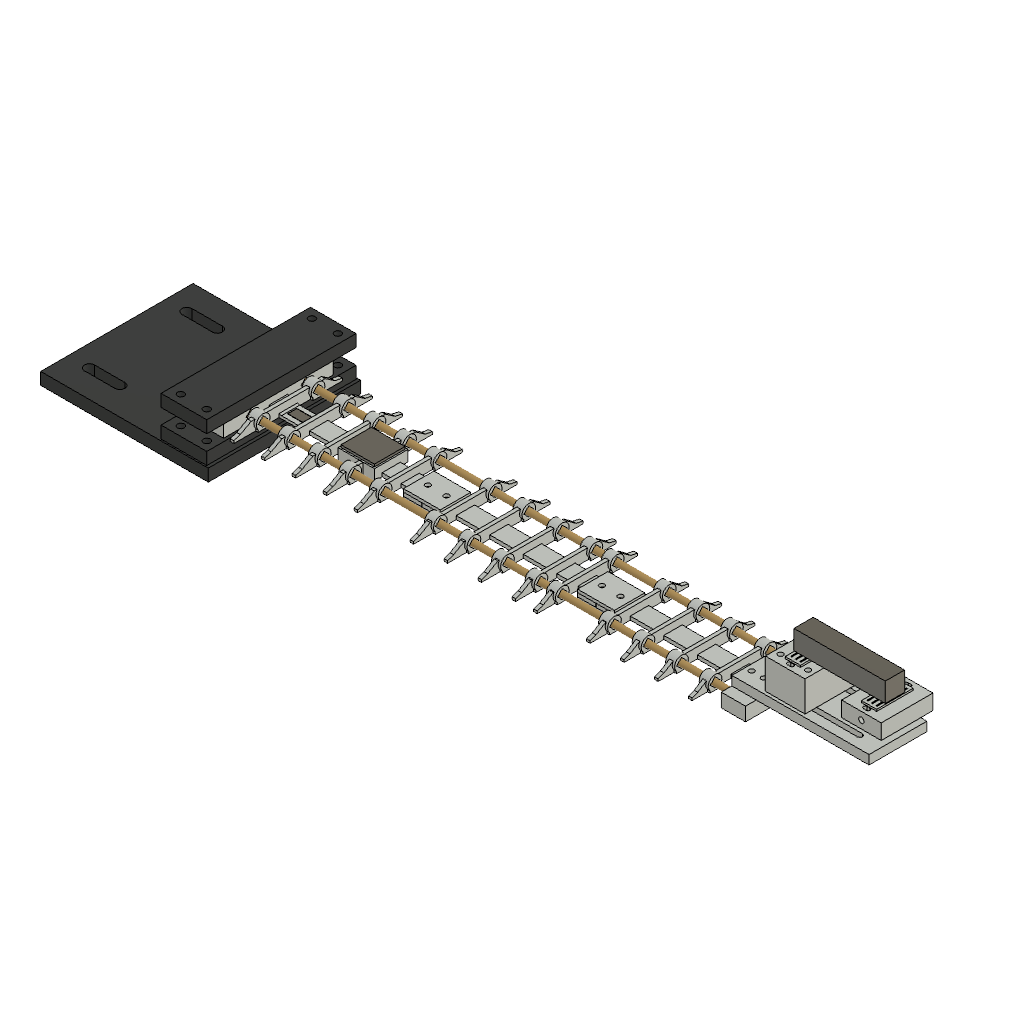
SkySafe_Assembly (Autodesk Fusion 360 design; units mm, degrees)
part number: 2026-10-10-17-05-36-424
part number: 2026-10-10-17-05-36-732
part number: 2026-10-10-17-05-38-635
part number: 2026-10-10-17-05-41-874
part number: 2026-10-10-17-05-46-497
part number: 2026-10-10-17-05-46-997
part number: 2026-10-10-17-05-49-609
part number: 2026-10-10-17-05-50-640
part number: 2026-10-10-17-05-52-144
part number: 2026-10-10-17-05-54-751
part number: 2026-10-10-17-05-56-746
part number: 2026-10-10-17-06-22-756
Autodesk Fusion 360 part; units mm, degrees
(part 1 of 3)
sketch "Continuous connecting strip sketch" plane through (0, 0, 0) normal (0, 0, 1) x (1, 0, 0) in component "01A Wing root - gauge and MPU"
  line L0 (23.95, -6) -> (128, -6)
  line L1 (128, -6) -> (128, 6)
  line L2 (128, 6) -> (23.95, 6)
  line L3 (23.95, 6) -> (23.95, -6)
extrude "Continuous connecting strip" add sketch "Continuous connecting strip sketch" along normal blind 1.8 makes body 1 in component "01A Wing root - gauge and MPU"
sketch "Root tongue sketch" plane through (0, 0, 0) normal (0, 0, 1) x (1, 0, 0) in component "01A Wing root - gauge and MPU"
  line L0 (0, -36) -> (24, -36)
  line L1 (24, -36) -> (24, 36)
  line L2 (24, 36) -> (0, 36)
  line L3 (0, 36) -> (0, -36)
extrude "Root tongue" add sketch "Root tongue sketch" along normal blind 10 bodies 1 in component "01A Wing root - gauge and MPU"
sketch "Reinforced strip beyond gauge sketch" plane through (0, 0, 0) normal (0, 0, 1) x (1, 0, 0) in component "01A Wing root - gauge and MPU"
  line L0 (48, -6) -> (128, -6)
  line L1 (128, -6) -> (128, 6)
  line L2 (128, 6) -> (48, 6)
  line L3 (48, 6) -> (48, -6)
extrude "Reinforced strip beyond gauge" add sketch "Reinforced strip beyond gauge sketch" along normal blind 2.4 bodies 1 in component "01A Wing root - gauge and MPU"
sketch "Root gauge shoulder sketch" plane through (0, 0, 0) normal (0, 1, 0) x (1, 0, 0) in component "01A Wing root - gauge and MPU"
  line L0 (23.95, 0) -> (32, 0)
  line L1 (32, 0) -> (32, -1.8)
  line L2 (32, -1.8) -> (23.95, -4)
  line L3 (23.95, -4) -> (23.95, 0)
extrude "Root tapered gauge shoulder" add sketch "Root gauge shoulder sketch" along normal mid plane 12 bodies 1 in component "01A Wing root - gauge and MPU"
ref_plane "WorkPlane1" through (28, 0, 0) normal (1, 0, 0) x (0, 1, 0) in component "01A Wing root - gauge and MPU"
sketch "Rib at 28 mm sketch" plane through (28, 0, 0) normal (1, 0, 0) x (0, 0, -1) in component "01A Wing root - gauge and MPU"
  line L0 (0, -35.6072) -> (0, 35.6072)
  line L1 (0, 35.6072) -> (-1.6, 35.6072)
  line L2 (-1.6, 35.6072) -> (-2.6, 30.6222)
  line L3 (-2.6, 30.6222) -> (-6.95, 24.2129)
  line L4 (-6.95, 24.2129) -> (-6.95, -24.2129)
  line L5 (-6.95, -24.2129) -> (-3, -31.3343)
  line L6 (-3, -31.3343) -> (-1.6, -35.6072)
  line L7 (-1.6, -35.6072) -> (0, -35.6072)
extrude "Rib at 28 mm" add sketch "Rib at 28 mm sketch" along normal blind 2.4 bodies 1 in component "01A Wing root - gauge and MPU"
ref_plane "WorkPlane2" through (26, 0, 0) normal (1, 0, 0) x (0, 1, 0) in component "01A Wing root - gauge and MPU"
sketch "front short guide at 28 mm sketch" plane through (26, 0, 0) normal (1, 0, 0) x (0, 0, -1) in component "01A Wing root - gauge and MPU"
  circle A0 centre (-4.5, -18) radius 4.5
extrude "front short guide at 28 mm" add sketch "front short guide at 28 mm sketch" along normal blind 6 bodies 1 in component "01A Wing root - gauge and MPU"
sketch "front guide foot at 28 mm sketch" plane through (0, 0, 0) normal (0, 0, 1) x (1, 0, 0) in component "01A Wing root - gauge and MPU"
  line L0 (26, -21.3) -> (32, -21.3)
  line L1 (32, -21.3) -> (32, -14.7)
  line L2 (32, -14.7) -> (26, -14.7)
  line L3 (26, -14.7) -> (26, -21.3)
extrude "front guide foot at 28 mm" add sketch "front guide foot at 28 mm sketch" along normal blind 1.4 bodies 1 in component "01A Wing root - gauge and MPU"
ref_plane "WorkPlane3" through (26, 0, 0) normal (1, 0, 0) x (0, 1, 0) in component "01A Wing root - gauge and MPU"
sketch "rear short guide at 28 mm sketch" plane through (26, 0, 0) normal (1, 0, 0) x (0, 0, -1) in component "01A Wing root - gauge and MPU"
  circle A0 centre (-4.5, 18) radius 4.5
extrude "rear short guide at 28 mm" add sketch "rear short guide at 28 mm sketch" along normal blind 6 bodies 1 in component "01A Wing root - gauge and MPU"
sketch "rear guide foot at 28 mm sketch" plane through (0, 0, 0) normal (0, 0, 1) x (1, 0, 0) in component "01A Wing root - gauge and MPU"
  line L0 (26, 14.7) -> (32, 14.7)
  line L1 (32, 14.7) -> (32, 21.3)
  line L2 (32, 21.3) -> (26, 21.3)
  line L3 (26, 21.3) -> (26, 14.7)
extrude "rear guide foot at 28 mm" add sketch "rear guide foot at 28 mm sketch" along normal blind 1.4 bodies 1 in component "01A Wing root - gauge and MPU"
ref_plane "WorkPlane4" through (48, 0, 0) normal (1, 0, 0) x (0, 1, 0) in component "01A Wing root - gauge and MPU"
sketch "Rib at 48 mm sketch" plane through (48, 0, 0) normal (1, 0, 0) x (0, 0, -1) in component "01A Wing root - gauge and MPU"
  line L0 (0, -35.3266) -> (0, 35.3266)
  line L1 (0, 35.3266) -> (-1.6, 35.3266)
  line L2 (-1.6, 35.3266) -> (-2.6, 30.3809)
  line L3 (-2.6, 30.3809) -> (-6.95, 24.0221)
  line L4 (-6.95, 24.0221) -> (-6.95, -24.0221)
  line L5 (-6.95, -24.0221) -> (-3, -31.0874)
  line L6 (-3, -31.0874) -> (-1.6, -35.3266)
  line L7 (-1.6, -35.3266) -> (0, -35.3266)
extrude "Rib at 48 mm" add sketch "Rib at 48 mm sketch" along normal blind 2.4 bodies 1 in component "01A Wing root - gauge and MPU"
ref_plane "WorkPlane5" through (46, 0, 0) normal (1, 0, 0) x (0, 1, 0) in component "01A Wing root - gauge and MPU"
sketch "front short guide at 48 mm sketch" plane through (46, 0, 0) normal (1, 0, 0) x (0, 0, -1) in component "01A Wing root - gauge and MPU"
  circle A0 centre (-4.5, -18) radius 4.5
extrude "front short guide at 48 mm" add sketch "front short guide at 48 mm sketch" along normal blind 6 bodies 1 in component "01A Wing root - gauge and MPU"
sketch "front guide foot at 48 mm sketch" plane through (0, 0, 0) normal (0, 0, 1) x (1, 0, 0) in component "01A Wing root - gauge and MPU"
  line L0 (46, -21.3) -> (52, -21.3)
  line L1 (52, -21.3) -> (52, -14.7)
  line L2 (52, -14.7) -> (46, -14.7)
  line L3 (46, -14.7) -> (46, -21.3)
extrude "front guide foot at 48 mm" add sketch "front guide foot at 48 mm sketch" along normal blind 1.4 bodies 1 in component "01A Wing root - gauge and MPU"
ref_plane "WorkPlane6" through (46, 0, 0) normal (1, 0, 0) x (0, 1, 0) in component "01A Wing root - gauge and MPU"
sketch "rear short guide at 48 mm sketch" plane through (46, 0, 0) normal (1, 0, 0) x (0, 0, -1) in component "01A Wing root - gauge and MPU"
  circle A0 centre (-4.5, 18) radius 4.5
extrude "rear short guide at 48 mm" add sketch "rear short guide at 48 mm sketch" along normal blind 6 bodies 1 in component "01A Wing root - gauge and MPU"
sketch "rear guide foot at 48 mm sketch" plane through (0, 0, 0) normal (0, 0, 1) x (1, 0, 0) in component "01A Wing root - gauge and MPU"
  line L0 (46, 14.7) -> (52, 14.7)
  line L1 (52, 14.7) -> (52, 21.3)
  line L2 (52, 21.3) -> (46, 21.3)
  line L3 (46, 21.3) -> (46, 14.7)
extrude "rear guide foot at 48 mm" add sketch "rear guide foot at 48 mm sketch" along normal blind 1.4 bodies 1 in component "01A Wing root - gauge and MPU"
ref_plane "WorkPlane7" through (68, 0, 0) normal (1, 0, 0) x (0, 1, 0) in component "01A Wing root - gauge and MPU"
sketch "Rib at 68 mm sketch" plane through (68, 0, 0) normal (1, 0, 0) x (0, 0, -1) in component "01A Wing root - gauge and MPU"
  line L0 (0, -35.046) -> (0, 35.046)
  line L1 (0, 35.046) -> (-1.6, 35.046)
  line L2 (-1.6, 35.046) -> (-2.6, 30.1396)
  line L3 (-2.6, 30.1396) -> (-6.95, 23.8313)
  line L4 (-6.95, 23.8313) -> (-6.95, -23.8313)
  line L5 (-6.95, -23.8313) -> (-3, -30.8405)
  line L6 (-3, -30.8405) -> (-1.6, -35.046)
  line L7 (-1.6, -35.046) -> (0, -35.046)
extrude "Rib at 68 mm" add sketch "Rib at 68 mm sketch" along normal blind 2.4 bodies 1 in component "01A Wing root - gauge and MPU"
ref_plane "WorkPlane8" through (66, 0, 0) normal (1, 0, 0) x (0, 1, 0) in component "01A Wing root - gauge and MPU"
sketch "front short guide at 68 mm sketch" plane through (66, 0, 0) normal (1, 0, 0) x (0, 0, -1) in component "01A Wing root - gauge and MPU"
  circle A0 centre (-4.5, -18) radius 4.5
extrude "front short guide at 68 mm" add sketch "front short guide at 68 mm sketch" along normal blind 6 bodies 1 in component "01A Wing root - gauge and MPU"
sketch "front guide foot at 68 mm sketch" plane through (0, 0, 0) normal (0, 0, 1) x (1, 0, 0) in component "01A Wing root - gauge and MPU"
  line L0 (66, -21.3) -> (72, -21.3)
  line L1 (72, -21.3) -> (72, -14.7)
  line L2 (72, -14.7) -> (66, -14.7)
  line L3 (66, -14.7) -> (66, -21.3)
extrude "front guide foot at 68 mm" add sketch "front guide foot at 68 mm sketch" along normal blind 1.4 bodies 1 in component "01A Wing root - gauge and MPU"
ref_plane "WorkPlane9" through (66, 0, 0) normal (1, 0, 0) x (0, 1, 0) in component "01A Wing root - gauge and MPU"
sketch "rear short guide at 68 mm sketch" plane through (66, 0, 0) normal (1, 0, 0) x (0, 0, -1) in component "01A Wing root - gauge and MPU"
  circle A0 centre (-4.5, 18) radius 4.5
extrude "rear short guide at 68 mm" add sketch "rear short guide at 68 mm sketch" along normal blind 6 bodies 1 in component "01A Wing root - gauge and MPU"
sketch "rear guide foot at 68 mm sketch" plane through (0, 0, 0) normal (0, 0, 1) x (1, 0, 0) in component "01A Wing root - gauge and MPU"
  line L0 (66, 14.7) -> (72, 14.7)
  line L1 (72, 14.7) -> (72, 21.3)
  line L2 (72, 21.3) -> (66, 21.3)
  line L3 (66, 21.3) -> (66, 14.7)
extrude "rear guide foot at 68 mm" add sketch "rear guide foot at 68 mm sketch" along normal blind 1.4 bodies 1 in component "01A Wing root - gauge and MPU"
ref_plane "WorkPlane10" through (88, 0, 0) normal (1, 0, 0) x (0, 1, 0) in component "01A Wing root - gauge and MPU"
sketch "Rib at 88 mm sketch" plane through (88, 0, 0) normal (1, 0, 0) x (0, 0, -1) in component "01A Wing root - gauge and MPU"
  line L0 (0, -34.7654) -> (0, 34.7654)
  line L1 (0, 34.7654) -> (-1.6, 34.7654)
  line L2 (-1.6, 34.7654) -> (-2.6, 29.8983)
  line L3 (-2.6, 29.8983) -> (-6.95, 23.6405)
  line L4 (-6.95, 23.6405) -> (-6.95, -23.6405)
  line L5 (-6.95, -23.6405) -> (-3, -30.5936)
  line L6 (-3, -30.5936) -> (-1.6, -34.7654)
  line L7 (-1.6, -34.7654) -> (0, -34.7654)
extrude "Rib at 88 mm" add sketch "Rib at 88 mm sketch" along normal blind 2.4 bodies 1 in component "01A Wing root - gauge and MPU"
ref_plane "WorkPlane11" through (86, 0, 0) normal (1, 0, 0) x (0, 1, 0) in component "01A Wing root - gauge and MPU"
sketch "front short guide at 88 mm sketch" plane through (86, 0, 0) normal (1, 0, 0) x (0, 0, -1) in component "01A Wing root - gauge and MPU"
  circle A0 centre (-4.5, -18) radius 4.5
extrude "front short guide at 88 mm" add sketch "front short guide at 88 mm sketch" along normal blind 6 bodies 1 in component "01A Wing root - gauge and MPU"
sketch "front guide foot at 88 mm sketch" plane through (0, 0, 0) normal (0, 0, 1) x (1, 0, 0) in component "01A Wing root - gauge and MPU"
  line L0 (86, -21.3) -> (92, -21.3)
  line L1 (92, -21.3) -> (92, -14.7)
  line L2 (92, -14.7) -> (86, -14.7)
  line L3 (86, -14.7) -> (86, -21.3)
extrude "front guide foot at 88 mm" add sketch "front guide foot at 88 mm sketch" along normal blind 1.4 bodies 1 in component "01A Wing root - gauge and MPU"
ref_plane "WorkPlane12" through (86, 0, 0) normal (1, 0, 0) x (0, 1, 0) in component "01A Wing root - gauge and MPU"
sketch "rear short guide at 88 mm sketch" plane through (86, 0, 0) normal (1, 0, 0) x (0, 0, -1) in component "01A Wing root - gauge and MPU"
  circle A0 centre (-4.5, 18) radius 4.5
extrude "rear short guide at 88 mm" add sketch "rear short guide at 88 mm sketch" along normal blind 6 bodies 1 in component "01A Wing root - gauge and MPU"
sketch "rear guide foot at 88 mm sketch" plane through (0, 0, 0) normal (0, 0, 1) x (1, 0, 0) in component "01A Wing root - gauge and MPU"
  line L0 (86, 14.7) -> (92, 14.7)
  line L1 (92, 14.7) -> (92, 21.3)
  line L2 (92, 21.3) -> (86, 21.3)
  line L3 (86, 21.3) -> (86, 14.7)
extrude "rear guide foot at 88 mm" add sketch "rear guide foot at 88 mm sketch" along normal blind 1.4 bodies 1 in component "01A Wing root - gauge and MPU"
ref_plane "WorkPlane13" through (108, 0, 0) normal (1, 0, 0) x (0, 1, 0) in component "01A Wing root - gauge and MPU"
sketch "Rib at 108 mm sketch" plane through (108, 0, 0) normal (1, 0, 0) x (0, 0, -1) in component "01A Wing root - gauge and MPU"
  line L0 (0, -34.4848) -> (0, 34.4848)
  line L1 (0, 34.4848) -> (-1.6, 34.4848)
  line L2 (-1.6, 34.4848) -> (-2.6, 29.657)
  line L3 (-2.6, 29.657) -> (-6.95, 23.4497)
  line L4 (-6.95, 23.4497) -> (-6.95, -23.4497)
  line L5 (-6.95, -23.4497) -> (-3, -30.3467)
  line L6 (-3, -30.3467) -> (-1.6, -34.4848)
  line L7 (-1.6, -34.4848) -> (0, -34.4848)
extrude "Rib at 108 mm" add sketch "Rib at 108 mm sketch" along normal blind 2.4 bodies 1 in component "01A Wing root - gauge and MPU"
ref_plane "WorkPlane14" through (106, 0, 0) normal (1, 0, 0) x (0, 1, 0) in component "01A Wing root - gauge and MPU"
sketch "front short guide at 108 mm sketch" plane through (106, 0, 0) normal (1, 0, 0) x (0, 0, -1) in component "01A Wing root - gauge and MPU"
  circle A0 centre (-4.5, -18) radius 4.5
extrude "front short guide at 108 mm" add sketch "front short guide at 108 mm sketch" along normal blind 6 bodies 1 in component "01A Wing root - gauge and MPU"
sketch "front guide foot at 108 mm sketch" plane through (0, 0, 0) normal (0, 0, 1) x (1, 0, 0) in component "01A Wing root - gauge and MPU"
  line L0 (106, -21.3) -> (112, -21.3)
  line L1 (112, -21.3) -> (112, -14.7)
  line L2 (112, -14.7) -> (106, -14.7)
  line L3 (106, -14.7) -> (106, -21.3)
extrude "front guide foot at 108 mm" add sketch "front guide foot at 108 mm sketch" along normal blind 1.4 bodies 1 in component "01A Wing root - gauge and MPU"
ref_plane "WorkPlane15" through (106, 0, 0) normal (1, 0, 0) x (0, 1, 0) in component "01A Wing root - gauge and MPU"
sketch "rear short guide at 108 mm sketch" plane through (106, 0, 0) normal (1, 0, 0) x (0, 0, -1) in component "01A Wing root - gauge and MPU"
  circle A0 centre (-4.5, 18) radius 4.5
extrude "rear short guide at 108 mm" add sketch "rear short guide at 108 mm sketch" along normal blind 6 bodies 1 in component "01A Wing root - gauge and MPU"
sketch "rear guide foot at 108 mm sketch" plane through (0, 0, 0) normal (0, 0, 1) x (1, 0, 0) in component "01A Wing root - gauge and MPU"
  line L0 (106, 14.7) -> (112, 14.7)
  line L1 (112, 14.7) -> (112, 21.3)
  line L2 (112, 21.3) -> (106, 21.3)
  line L3 (106, 21.3) -> (106, 14.7)
extrude "rear guide foot at 108 mm" add sketch "rear guide foot at 108 mm sketch" along normal blind 1.4 bodies 1 in component "01A Wing root - gauge and MPU"
sketch "Joint landing at 116.0 sketch" plane through (0, 0, 0) normal (0, 0, 1) x (1, 0, 0) in component "01A Wing root - gauge and MPU"
  line L0 (116, -10) -> (128, -10)
  line L1 (128, -10) -> (128, 10)
  line L2 (128, 10) -> (116, 10)
  line L3 (116, 10) -> (116, -10)
extrude "Joint landing at 116.0" add sketch "Joint landing at 116.0 sketch" along normal blind 2.4 bodies 1 in component "01A Wing root - gauge and MPU"
ref_plane "WorkPlane16" through (0, 0, -0.05) normal (0, 0, 1) x (1, 0, 0) in component "01A Wing root - gauge and MPU"
sketch "Joint bolt at 122.0 sketch" plane through (0, 0, -0.05) normal (0, 0, 1) x (1, 0, 0) in component "01A Wing root - gauge and MPU"
  circle A0 centre (122, 0) radius 1.7
  dimension "d102" = 3.4
  measures "d102" diameter of A0
extrude "Joint bolt at 122.0" cut sketch "Joint bolt at 122.0 sketch" along normal blind 2.5 bodies 1 in component "01A Wing root - gauge and MPU"
sketch "MPU strap landing sketch" plane through (0, 0, 0) normal (0, 0, 1) x (1, 0, 0) in component "01A Wing root - gauge and MPU"
  line L0 (74, -11) -> (98, -11)
  line L1 (98, -11) -> (98, 11)
  line L2 (98, 11) -> (74, 11)
  line L3 (74, 11) -> (74, -11)
extrude "MPU strap landing" add sketch "MPU strap landing sketch" along normal blind 7.2 bodies 1 in component "01A Wing root - gauge and MPU"
ref_plane "WorkPlane17" through (0, 0, -0.05) normal (0, 0, 1) x (1, 0, 0) in component "01A Wing root - gauge and MPU"
sketch "Root registration -8 sketch" plane through (0, 0, -0.05) normal (0, 0, 1) x (1, 0, 0) in component "01A Wing root - gauge and MPU"
  circle A0 centre (8, -8) radius 1.7
  dimension "d109" = 3.4
  measures "d109" diameter of A0
extrude "Root registration -8" cut sketch "Root registration -8 sketch" along normal blind 10.1 bodies 1 in component "01A Wing root - gauge and MPU"
ref_plane "WorkPlane18" through (0, 0, -0.05) normal (0, 0, 1) x (1, 0, 0) in component "01A Wing root - gauge and MPU"
sketch "Root registration 8 sketch" plane through (0, 0, -0.05) normal (0, 0, 1) x (1, 0, 0) in component "01A Wing root - gauge and MPU"
  circle A0 centre (8, 8) radius 1.7
  dimension "d114" = 3.4
  measures "d114" diameter of A0
extrude "Root registration 8" cut sketch "Root registration 8 sketch" along normal blind 10.1 bodies 1 in component "01A Wing root - gauge and MPU"
ref_plane "WorkPlane19" through (0, 0, -0.05) normal (0, 0, 1) x (1, 0, 0) in component "01A Wing root - gauge and MPU"
sketch "Board tie 78 -7 sketch" plane through (0, 0, -0.05) normal (0, 0, 1) x (1, 0, 0) in component "01A Wing root - gauge and MPU"
  arc A0 (77.5, -5.9) -> (77.5, -8.1) centre (77.5, -7) ccw
  line L0 (77.5, -5.9) -> (78.5, -5.9)
  arc A1 (78.5, -8.1) -> (78.5, -5.9) centre (78.5, -7) ccw
  line L1 (78.5, -8.1) -> (77.5, -8.1)
extrude "Board tie 78 -7" cut sketch "Board tie 78 -7 sketch" along normal blind 7.3 bodies 1 in component "01A Wing root - gauge and MPU"
ref_plane "WorkPlane20" through (0, 0, -0.05) normal (0, 0, 1) x (1, 0, 0) in component "01A Wing root - gauge and MPU"
sketch "Board tie 78 7 sketch" plane through (0, 0, -0.05) normal (0, 0, 1) x (1, 0, 0) in component "01A Wing root - gauge and MPU"
  arc A0 (77.5, 8.1) -> (77.5, 5.9) centre (77.5, 7) ccw
  line L0 (77.5, 8.1) -> (78.5, 8.1)
  arc A1 (78.5, 5.9) -> (78.5, 8.1) centre (78.5, 7) ccw
  line L1 (78.5, 5.9) -> (77.5, 5.9)
extrude "Board tie 78 7" cut sketch "Board tie 78 7 sketch" along normal blind 7.3 bodies 1 in component "01A Wing root - gauge and MPU"
ref_plane "WorkPlane21" through (0, 0, -0.05) normal (0, 0, 1) x (1, 0, 0) in component "01A Wing root - gauge and MPU"
sketch "Board tie 94 -7 sketch" plane through (0, 0, -0.05) normal (0, 0, 1) x (1, 0, 0) in component "01A Wing root - gauge and MPU"
  arc A0 (93.5, -5.9) -> (93.5, -8.1) centre (93.5, -7) ccw
  line L0 (93.5, -5.9) -> (94.5, -5.9)
  arc A1 (94.5, -8.1) -> (94.5, -5.9) centre (94.5, -7) ccw
  line L1 (94.5, -8.1) -> (93.5, -8.1)
extrude "Board tie 94 -7" cut sketch "Board tie 94 -7 sketch" along normal blind 7.3 bodies 1 in component "01A Wing root - gauge and MPU"
ref_plane "WorkPlane22" through (0, 0, -0.05) normal (0, 0, 1) x (1, 0, 0) in component "01A Wing root - gauge and MPU"
sketch "Board tie 94 7 sketch" plane through (0, 0, -0.05) normal (0, 0, 1) x (1, 0, 0) in component "01A Wing root - gauge and MPU"
  arc A0 (93.5, 8.1) -> (93.5, 5.9) centre (93.5, 7) ccw
  line L0 (93.5, 8.1) -> (94.5, 8.1)
  arc A1 (94.5, 5.9) -> (94.5, 8.1) centre (94.5, 7) ccw
  line L1 (94.5, 5.9) -> (93.5, 5.9)
extrude "Board tie 94 7" cut sketch "Board tie 94 7 sketch" along normal blind 7.3 bodies 1 in component "01A Wing root - gauge and MPU"
ref_plane "WorkPlane23" through (-0.05, 0, 0) normal (1, 0, 0) x (0, 1, 0) in component "01A Wing root - gauge and MPU"
sketch "front diamond bamboo passage sketch" plane through (-0.05, 0, 0) normal (1, 0, 0) x (0, 0, -1) in component "01A Wing root - gauge and MPU"
  line L0 (-4.5, -21.182) -> (-1.318, -18)
  line L1 (-1.318, -18) -> (-4.5, -14.818)
  line L2 (-4.5, -14.818) -> (-7.682, -18)
  line L3 (-7.682, -18) -> (-4.5, -21.182)
  line L4 (-4.5, -21.182) -> (-4.5, -14.818) construction
  line L5 (-1.318, -18) -> (-7.682, -18) construction
  point P0 (-4.5, -18)
  dimension "d135" = 6.364
  constraint vertical L4
  constraint horizontal L5
  constraint midpoint L4 P0
  constraint midpoint L5 P0
  constraint equal L4 L5
  measures "d135" distance of L0.end L2.end
extrude "front diamond bamboo passage" cut sketch "front diamond bamboo passage sketch" along normal blind 128.1 bodies 1 in component "01A Wing root - gauge and MPU"
ref_plane "WorkPlane24" through (-0.05, 0, 0) normal (1, 0, 0) x (0, 1, 0) in component "01A Wing root - gauge and MPU"
sketch "rear diamond bamboo passage sketch" plane through (-0.05, 0, 0) normal (1, 0, 0) x (0, 0, -1) in component "01A Wing root - gauge and MPU"
  line L0 (-4.5, 14.818) -> (-1.318, 18)
  line L1 (-1.318, 18) -> (-4.5, 21.182)
  line L2 (-4.5, 21.182) -> (-7.682, 18)
  line L3 (-7.682, 18) -> (-4.5, 14.818)
  line L4 (-4.5, 14.818) -> (-4.5, 21.182) construction
  line L5 (-1.318, 18) -> (-7.682, 18) construction
  point P0 (-4.5, 18)
  dimension "d140" = 6.364
  constraint vertical L4
  constraint horizontal L5
  constraint midpoint L4 P0
  constraint midpoint L5 P0
  constraint equal L4 L5
  measures "d140" distance of L0.end L2.end
extrude "rear diamond bamboo passage" cut sketch "rear diamond bamboo passage sketch" along normal blind 128.1 bodies 1 in component "01A Wing root - gauge and MPU"
sketch "Continuous connecting strip sketch (2)" plane through (0, 0, 0) normal (0, 0, 1) x (1, 0, 0) in component "01B Wing middle"
  line L0 (0, -6) -> (114, -6)
  line L1 (114, -6) -> (114, 6)
  line L2 (114, 6) -> (0, 6)
  line L3 (0, 6) -> (0, -6)
extrude "Continuous connecting strip'" add sketch "Continuous connecting strip sketch (2)" along normal blind 2.4 separate body makes body 2 in component "01B Wing middle"
ref_plane "WorkPlane1" through (16, 0, 0) normal (1, 0, 0) x (0, 1, 0) in component "01B Wing middle"
sketch "Rib at 16 mm sketch" plane through (16, 0, 0) normal (1, 0, 0) x (0, 0, -1) in component "01B Wing middle"
  line L0 (0, -33.977) -> (0, 33.977)
  line L1 (0, 33.977) -> (-1.6, 33.977)
  line L2 (-1.6, 33.977) -> (-2.6, 29.2202)
  line L3 (-2.6, 29.2202) -> (-6.95, 23.1044)
  line L4 (-6.95, 23.1044) -> (-6.95, -23.1044)
  line L5 (-6.95, -23.1044) -> (-3, -29.8998)
  line L6 (-3, -29.8998) -> (-1.6, -33.977)
  line L7 (-1.6, -33.977) -> (0, -33.977)
extrude "Rib at 16 mm" add sketch "Rib at 16 mm sketch" along normal blind 2.4 bodies 2 in component "01B Wing middle"
ref_plane "WorkPlane2" through (14, 0, 0) normal (1, 0, 0) x (0, 1, 0) in component "01B Wing middle"
sketch "front short guide at 16 mm sketch" plane through (14, 0, 0) normal (1, 0, 0) x (0, 0, -1) in component "01B Wing middle"
  circle A0 centre (-4.5, -18) radius 4.5
extrude "front short guide at 16 mm" add sketch "front short guide at 16 mm sketch" along normal blind 6 bodies 2 in component "01B Wing middle"
sketch "front guide foot at 16 mm sketch" plane through (0, 0, 0) normal (0, 0, 1) x (1, 0, 0) in component "01B Wing middle"
  line L0 (14, -21.3) -> (20, -21.3)
  line L1 (20, -21.3) -> (20, -14.7)
  line L2 (20, -14.7) -> (14, -14.7)
  line L3 (14, -14.7) -> (14, -21.3)
extrude "front guide foot at 16 mm" add sketch "front guide foot at 16 mm sketch" along normal blind 1.4 bodies 2 in component "01B Wing middle"
ref_plane "WorkPlane3" through (14, 0, 0) normal (1, 0, 0) x (0, 1, 0) in component "01B Wing middle"
sketch "rear short guide at 16 mm sketch" plane through (14, 0, 0) normal (1, 0, 0) x (0, 0, -1) in component "01B Wing middle"
  circle A0 centre (-4.5, 18) radius 4.5
extrude "rear short guide at 16 mm" add sketch "rear short guide at 16 mm sketch" along normal blind 6 bodies 2 in component "01B Wing middle"
sketch "rear guide foot at 16 mm sketch" plane through (0, 0, 0) normal (0, 0, 1) x (1, 0, 0) in component "01B Wing middle"
  line L0 (14, 14.7) -> (20, 14.7)
  line L1 (20, 14.7) -> (20, 21.3)
  line L2 (20, 21.3) -> (14, 21.3)
  line L3 (14, 21.3) -> (14, 14.7)
extrude "rear guide foot at 16 mm" add sketch "rear guide foot at 16 mm sketch" along normal blind 1.4 bodies 2 in component "01B Wing middle"
ref_plane "WorkPlane4" through (38, 0, 0) normal (1, 0, 0) x (0, 1, 0) in component "01B Wing middle"
sketch "Rib at 38 mm sketch" plane through (38, 0, 0) normal (1, 0, 0) x (0, 0, -1) in component "01B Wing middle"
  line L0 (0, -33.6684) -> (0, 33.6684)
  line L1 (0, 33.6684) -> (-1.6, 33.6684)
  line L2 (-1.6, 33.6684) -> (-2.6, 28.9548)
  line L3 (-2.6, 28.9548) -> (-6.95, 22.8945)
  line L4 (-6.95, 22.8945) -> (-6.95, -22.8945)
  line L5 (-6.95, -22.8945) -> (-3, -29.6281)
  line L6 (-3, -29.6281) -> (-1.6, -33.6684)
  line L7 (-1.6, -33.6684) -> (0, -33.6684)
extrude "Rib at 38 mm" add sketch "Rib at 38 mm sketch" along normal blind 2.4 bodies 2 in component "01B Wing middle"
ref_plane "WorkPlane5" through (36, 0, 0) normal (1, 0, 0) x (0, 1, 0) in component "01B Wing middle"
sketch "front short guide at 38 mm sketch" plane through (36, 0, 0) normal (1, 0, 0) x (0, 0, -1) in component "01B Wing middle"
  circle A0 centre (-4.5, -18) radius 4.5
extrude "front short guide at 38 mm" add sketch "front short guide at 38 mm sketch" along normal blind 6 bodies 2 in component "01B Wing middle"
sketch "front guide foot at 38 mm sketch" plane through (0, 0, 0) normal (0, 0, 1) x (1, 0, 0) in component "01B Wing middle"
  line L0 (36, -21.3) -> (42, -21.3)
  line L1 (42, -21.3) -> (42, -14.7)
  line L2 (42, -14.7) -> (36, -14.7)
  line L3 (36, -14.7) -> (36, -21.3)
extrude "front guide foot at 38 mm" add sketch "front guide foot at 38 mm sketch" along normal blind 1.4 bodies 2 in component "01B Wing middle"
ref_plane "WorkPlane6" through (36, 0, 0) normal (1, 0, 0) x (0, 1, 0) in component "01B Wing middle"
sketch "rear short guide at 38 mm sketch" plane through (36, 0, 0) normal (1, 0, 0) x (0, 0, -1) in component "01B Wing middle"
  circle A0 centre (-4.5, 18) radius 4.5
extrude "rear short guide at 38 mm" add sketch "rear short guide at 38 mm sketch" along normal blind 6 bodies 2 in component "01B Wing middle"
sketch "rear guide foot at 38 mm sketch" plane through (0, 0, 0) normal (0, 0, 1) x (1, 0, 0) in component "01B Wing middle"
  line L0 (36, 14.7) -> (42, 14.7)
  line L1 (42, 14.7) -> (42, 21.3)
  line L2 (42, 21.3) -> (36, 21.3)
  line L3 (36, 21.3) -> (36, 14.7)
extrude "rear guide foot at 38 mm" add sketch "rear guide foot at 38 mm sketch" along normal blind 1.4 bodies 2 in component "01B Wing middle"
ref_plane "WorkPlane7" through (60, 0, 0) normal (1, 0, 0) x (0, 1, 0) in component "01B Wing middle"
sketch "Rib at 60 mm sketch" plane through (60, 0, 0) normal (1, 0, 0) x (0, 0, -1) in component "01B Wing middle"
  line L0 (0, -33.3597) -> (0, 33.3597)
  line L1 (0, 33.3597) -> (-1.6, 33.3597)
  line L2 (-1.6, 33.3597) -> (-2.6, 28.6893)
  line L3 (-2.6, 28.6893) -> (-6.95, 22.6846)
  line L4 (-6.95, 22.6846) -> (-6.95, -22.6846)
  line L5 (-6.95, -22.6846) -> (-3, -29.3565)
  line L6 (-3, -29.3565) -> (-1.6, -33.3597)
  line L7 (-1.6, -33.3597) -> (0, -33.3597)
extrude "Rib at 60 mm" add sketch "Rib at 60 mm sketch" along normal blind 2.4 bodies 2 in component "01B Wing middle"
ref_plane "WorkPlane8" through (58, 0, 0) normal (1, 0, 0) x (0, 1, 0) in component "01B Wing middle"
sketch "front short guide at 60 mm sketch" plane through (58, 0, 0) normal (1, 0, 0) x (0, 0, -1) in component "01B Wing middle"
  circle A0 centre (-4.5, -18) radius 4.5
extrude "front short guide at 60 mm" add sketch "front short guide at 60 mm sketch" along normal blind 6 bodies 2 in component "01B Wing middle"
sketch "front guide foot at 60 mm sketch" plane through (0, 0, 0) normal (0, 0, 1) x (1, 0, 0) in component "01B Wing middle"
  line L0 (58, -21.3) -> (64, -21.3)
  line L1 (64, -21.3) -> (64, -14.7)
  line L2 (64, -14.7) -> (58, -14.7)
  line L3 (58, -14.7) -> (58, -21.3)
extrude "front guide foot at 60 mm" add sketch "front guide foot at 60 mm sketch" along normal blind 1.4 bodies 2 in component "01B Wing middle"
ref_plane "WorkPlane9" through (58, 0, 0) normal (1, 0, 0) x (0, 1, 0) in component "01B Wing middle"
sketch "rear short guide at 60 mm sketch" plane through (58, 0, 0) normal (1, 0, 0) x (0, 0, -1) in component "01B Wing middle"
  circle A0 centre (-4.5, 18) radius 4.5
extrude "rear short guide at 60 mm" add sketch "rear short guide at 60 mm sketch" along normal blind 6 bodies 2 in component "01B Wing middle"
sketch "rear guide foot at 60 mm sketch" plane through (0, 0, 0) normal (0, 0, 1) x (1, 0, 0) in component "01B Wing middle"
  line L0 (58, 14.7) -> (64, 14.7)
  line L1 (64, 14.7) -> (64, 21.3)
  line L2 (64, 21.3) -> (58, 21.3)
  line L3 (58, 21.3) -> (58, 14.7)
extrude "rear guide foot at 60 mm" add sketch "rear guide foot at 60 mm sketch" along normal blind 1.4 bodies 2 in component "01B Wing middle"
ref_plane "WorkPlane10" through (82, 0, 0) normal (1, 0, 0) x (0, 1, 0) in component "01B Wing middle"
sketch "Rib at 82 mm sketch" plane through (82, 0, 0) normal (1, 0, 0) x (0, 0, -1) in component "01B Wing middle"
  line L0 (0, -33.0511) -> (0, 33.0511)
  line L1 (0, 33.0511) -> (-1.6, 33.0511)
  line L2 (-1.6, 33.0511) -> (-2.6, 28.4239)
  line L3 (-2.6, 28.4239) -> (-6.95, 22.4747)
  line L4 (-6.95, 22.4747) -> (-6.95, -22.4747)
  line L5 (-6.95, -22.4747) -> (-3, -29.0849)
  line L6 (-3, -29.0849) -> (-1.6, -33.0511)
  line L7 (-1.6, -33.0511) -> (0, -33.0511)
extrude "Rib at 82 mm" add sketch "Rib at 82 mm sketch" along normal blind 2.4 bodies 2 in component "01B Wing middle"
ref_plane "WorkPlane11" through (80, 0, 0) normal (1, 0, 0) x (0, 1, 0) in component "01B Wing middle"
sketch "front short guide at 82 mm sketch" plane through (80, 0, 0) normal (1, 0, 0) x (0, 0, -1) in component "01B Wing middle"
  circle A0 centre (-4.5, -18) radius 4.5
extrude "front short guide at 82 mm" add sketch "front short guide at 82 mm sketch" along normal blind 6 bodies 2 in component "01B Wing middle"
sketch "front guide foot at 82 mm sketch" plane through (0, 0, 0) normal (0, 0, 1) x (1, 0, 0) in component "01B Wing middle"
  line L0 (80, -21.3) -> (86, -21.3)
  line L1 (86, -21.3) -> (86, -14.7)
  line L2 (86, -14.7) -> (80, -14.7)
  line L3 (80, -14.7) -> (80, -21.3)
extrude "front guide foot at 82 mm" add sketch "front guide foot at 82 mm sketch" along normal blind 1.4 bodies 2 in component "01B Wing middle"
ref_plane "WorkPlane12" through (80, 0, 0) normal (1, 0, 0) x (0, 1, 0) in component "01B Wing middle"
sketch "rear short guide at 82 mm sketch" plane through (80, 0, 0) normal (1, 0, 0) x (0, 0, -1) in component "01B Wing middle"
  circle A0 centre (-4.5, 18) radius 4.5
extrude "rear short guide at 82 mm" add sketch "rear short guide at 82 mm sketch" along normal blind 6 bodies 2 in component "01B Wing middle"
sketch "rear guide foot at 82 mm sketch" plane through (0, 0, 0) normal (0, 0, 1) x (1, 0, 0) in component "01B Wing middle"
  line L0 (80, 14.7) -> (86, 14.7)
  line L1 (86, 14.7) -> (86, 21.3)
  line L2 (86, 21.3) -> (80, 21.3)
  line L3 (80, 21.3) -> (80, 14.7)
extrude "rear guide foot at 82 mm" add sketch "rear guide foot at 82 mm sketch" along normal blind 1.4 bodies 2 in component "01B Wing middle"
ref_plane "WorkPlane13" through (96, 0, 0) normal (1, 0, 0) x (0, 1, 0) in component "01B Wing middle"
sketch "Rib at 96 mm sketch" plane through (96, 0, 0) normal (1, 0, 0) x (0, 0, -1) in component "01B Wing middle"
  line L0 (0, -32.8547) -> (0, 32.8547)
  line L1 (0, 32.8547) -> (-1.6, 32.8547)
  line L2 (-1.6, 32.8547) -> (-2.6, 28.255)
  line L3 (-2.6, 28.255) -> (-6.95, 22.3412)
  line L4 (-6.95, 22.3412) -> (-6.95, -22.3412)
  line L5 (-6.95, -22.3412) -> (-3, -28.9121)
  line L6 (-3, -28.9121) -> (-1.6, -32.8547)
  line L7 (-1.6, -32.8547) -> (0, -32.8547)
extrude "Rib at 96 mm" add sketch "Rib at 96 mm sketch" along normal blind 2.4 bodies 2 in component "01B Wing middle"
ref_plane "WorkPlane14" through (94, 0, 0) normal (1, 0, 0) x (0, 1, 0) in component "01B Wing middle"
sketch "front short guide at 96 mm sketch" plane through (94, 0, 0) normal (1, 0, 0) x (0, 0, -1) in component "01B Wing middle"
  circle A0 centre (-4.5, -18) radius 4.5
extrude "front short guide at 96 mm" add sketch "front short guide at 96 mm sketch" along normal blind 6 bodies 2 in component "01B Wing middle"
sketch "front guide foot at 96 mm sketch" plane through (0, 0, 0) normal (0, 0, 1) x (1, 0, 0) in component "01B Wing middle"
  line L0 (94, -21.3) -> (100, -21.3)
  line L1 (100, -21.3) -> (100, -14.7)
  line L2 (100, -14.7) -> (94, -14.7)
  line L3 (94, -14.7) -> (94, -21.3)
extrude "front guide foot at 96 mm" add sketch "front guide foot at 96 mm sketch" along normal blind 1.4 bodies 2 in component "01B Wing middle"
ref_plane "WorkPlane15" through (94, 0, 0) normal (1, 0, 0) x (0, 1, 0) in component "01B Wing middle"
sketch "rear short guide at 96 mm sketch" plane through (94, 0, 0) normal (1, 0, 0) x (0, 0, -1) in component "01B Wing middle"
  circle A0 centre (-4.5, 18) radius 4.5
extrude "rear short guide at 96 mm" add sketch "rear short guide at 96 mm sketch" along normal blind 6 bodies 2 in component "01B Wing middle"
sketch "rear guide foot at 96 mm sketch" plane through (0, 0, 0) normal (0, 0, 1) x (1, 0, 0) in component "01B Wing middle"
  line L0 (94, 14.7) -> (100, 14.7)
  line L1 (100, 14.7) -> (100, 21.3)
  line L2 (100, 21.3) -> (94, 21.3)
  line L3 (94, 21.3) -> (94, 14.7)
extrude "rear guide foot at 96 mm" add sketch "rear guide foot at 96 mm sketch" along normal blind 1.4 bodies 2 in component "01B Wing middle"
sketch "Joint landing at 0 sketch" plane through (0, 0, 0) normal (0, 0, 1) x (1, 0, 0) in component "01B Wing middle"
  line L0 (0, -10) -> (12, -10)
  line L1 (12, -10) -> (12, 10)
  line L2 (12, 10) -> (0, 10)
  line L3 (0, 10) -> (0, -10)
extrude "Joint landing at 0" add sketch "Joint landing at 0 sketch" along normal blind 2.4 bodies 2 in component "01B Wing middle"
ref_plane "WorkPlane16" through (0, 0, -0.05) normal (0, 0, 1) x (1, 0, 0) in component "01B Wing middle"
sketch "Joint bolt at 6 sketch" plane through (0, 0, -0.05) normal (0, 0, 1) x (1, 0, 0) in component "01B Wing middle"
  circle A0 centre (6, 0) radius 1.7
  dimension "d229" = 3.4
  measures "d229" diameter of A0
extrude "Joint bolt at 6" cut sketch "Joint bolt at 6 sketch" along normal blind 2.5 bodies 2 in component "01B Wing middle"
sketch "Joint landing at 102.0 sketch" plane through (0, 0, 0) normal (0, 0, 1) x (1, 0, 0) in component "01B Wing middle"
  line L0 (102, -10) -> (114, -10)
  line L1 (114, -10) -> (114, 10)
  line L2 (114, 10) -> (102, 10)
  line L3 (102, 10) -> (102, -10)
extrude "Joint landing at 102.0" add sketch "Joint landing at 102.0 sketch" along normal blind 2.4 bodies 2 in component "01B Wing middle"
ref_plane "WorkPlane17" through (0, 0, -0.05) normal (0, 0, 1) x (1, 0, 0) in component "01B Wing middle"
sketch "Joint bolt at 108.0 sketch" plane through (0, 0, -0.05) normal (0, 0, 1) x (1, 0, 0) in component "01B Wing middle"
  circle A0 centre (108, 0) radius 1.7
  dimension "d236" = 3.4
  measures "d236" diameter of A0
extrude "Joint bolt at 108.0" cut sketch "Joint bolt at 108.0 sketch" along normal blind 2.5 bodies 2 in component "01B Wing middle"
ref_plane "WorkPlane18" through (-0.05, 0, 0) normal (1, 0, 0) x (0, 1, 0) in component "01B Wing middle"
sketch "front diamond bamboo passage sketch (2)" plane through (-0.05, 0, 0) normal (1, 0, 0) x (0, 0, -1) in component "01B Wing middle"
  line L0 (-4.5, -21.182) -> (-1.318, -18)
  line L1 (-1.318, -18) -> (-4.5, -14.818)
  line L2 (-4.5, -14.818) -> (-7.682, -18)
  line L3 (-7.682, -18) -> (-4.5, -21.182)
  line L4 (-4.5, -21.182) -> (-4.5, -14.818) construction
  line L5 (-1.318, -18) -> (-7.682, -18) construction
  point P0 (-4.5, -18)
  dimension "d241" = 6.364
  constraint vertical L4
  constraint horizontal L5
  constraint midpoint L4 P0
  constraint midpoint L5 P0
  constraint equal L4 L5
  measures "d241" distance of L0.end L2.end
extrude "front diamond bamboo passage'" cut sketch "front diamond bamboo passage sketch (2)" along normal blind 114.1 bodies 2 in component "01B Wing middle"
ref_plane "WorkPlane19" through (-0.05, 0, 0) normal (1, 0, 0) x (0, 1, 0) in component "01B Wing middle"
sketch "rear diamond bamboo passage sketch (2)" plane through (-0.05, 0, 0) normal (1, 0, 0) x (0, 0, -1) in component "01B Wing middle"
  line L0 (-4.5, 14.818) -> (-1.318, 18)
  line L1 (-1.318, 18) -> (-4.5, 21.182)
  line L2 (-4.5, 21.182) -> (-7.682, 18)
  line L3 (-7.682, 18) -> (-4.5, 14.818)
  line L4 (-4.5, 14.818) -> (-4.5, 21.182) construction
  line L5 (-1.318, 18) -> (-7.682, 18) construction
  point P0 (-4.5, 18)
  dimension "d246" = 6.364
  constraint vertical L4
  constraint horizontal L5
  constraint midpoint L4 P0
  constraint midpoint L5 P0
  constraint equal L4 L5
  measures "d246" distance of L0.end L2.end
extrude "rear diamond bamboo passage'" cut sketch "rear diamond bamboo passage sketch (2)" along normal blind 114.1 bodies 2 in component "01B Wing middle"
sketch "Continuous connecting strip sketch (3)" plane through (0, 0, 0) normal (0, 0, 1) x (1, 0, 0) in component "01C Wing tip - load adapter"
  line L0 (0, -6) -> (114, -6)
  line L1 (114, -6) -> (114, 6)
  line L2 (114, 6) -> (0, 6)
  line L3 (0, 6) -> (0, -6)
extrude "Continuous connecting strip''" add sketch "Continuous connecting strip sketch (3)" along normal blind 2.4 separate body makes body 3 in component "01C Wing tip - load adapter"
ref_plane "WorkPlane1" through (16, 0, 0) normal (1, 0, 0) x (0, 1, 0) in component "01C Wing tip - load adapter"
sketch "Rib at 16 mm sketch (2)" plane through (16, 0, 0) normal (1, 0, 0) x (0, 0, -1) in component "01C Wing tip - load adapter"
  line L0 (0, -32.3749) -> (0, 32.3749)
  line L1 (0, 32.3749) -> (-1.6, 32.3749)
  line L2 (-1.6, 32.3749) -> (-2.6, 27.8424)
  line L3 (-2.6, 27.8424) -> (-6.95, 22.0149)
  line L4 (-6.95, 22.0149) -> (-6.95, -22.0149)
  line L5 (-6.95, -22.0149) -> (-3, -28.4899)
  line L6 (-3, -28.4899) -> (-1.6, -32.3749)
  line L7 (-1.6, -32.3749) -> (0, -32.3749)
extrude "Rib at 16 mm'" add sketch "Rib at 16 mm sketch (2)" along normal blind 2.4 bodies 3 in component "01C Wing tip - load adapter"
ref_plane "WorkPlane2" through (14, 0, 0) normal (1, 0, 0) x (0, 1, 0) in component "01C Wing tip - load adapter"
sketch "front short guide at 16 mm sketch (2)" plane through (14, 0, 0) normal (1, 0, 0) x (0, 0, -1) in component "01C Wing tip - load adapter"
  circle A0 centre (-4.5, -18) radius 4.5
extrude "front short guide at 16 mm'" add sketch "front short guide at 16 mm sketch (2)" along normal blind 6 bodies 3 in component "01C Wing tip - load adapter"
sketch "front guide foot at 16 mm sketch (2)" plane through (0, 0, 0) normal (0, 0, 1) x (1, 0, 0) in component "01C Wing tip - load adapter"
  line L0 (14, -21.3) -> (20, -21.3)
  line L1 (20, -21.3) -> (20, -14.7)
  line L2 (20, -14.7) -> (14, -14.7)
  line L3 (14, -14.7) -> (14, -21.3)
extrude "front guide foot at 16 mm'" add sketch "front guide foot at 16 mm sketch (2)" along normal blind 1.4 bodies 3 in component "01C Wing tip - load adapter"
ref_plane "WorkPlane3" through (14, 0, 0) normal (1, 0, 0) x (0, 1, 0) in component "01C Wing tip - load adapter"
sketch "rear short guide at 16 mm sketch (2)" plane through (14, 0, 0) normal (1, 0, 0) x (0, 0, -1) in component "01C Wing tip - load adapter"
  circle A0 centre (-4.5, 18) radius 4.5
extrude "rear short guide at 16 mm'" add sketch "rear short guide at 16 mm sketch (2)" along normal blind 6 bodies 3 in component "01C Wing tip - load adapter"
sketch "rear guide foot at 16 mm sketch (2)" plane through (0, 0, 0) normal (0, 0, 1) x (1, 0, 0) in component "01C Wing tip - load adapter"
  line L0 (14, 14.7) -> (20, 14.7)
  line L1 (20, 14.7) -> (20, 21.3)
  line L2 (20, 21.3) -> (14, 21.3)
  line L3 (14, 21.3) -> (14, 14.7)
extrude "rear guide foot at 16 mm'" add sketch "rear guide foot at 16 mm sketch (2)" along normal blind 1.4 bodies 3 in component "01C Wing tip - load adapter"
ref_plane "WorkPlane4" through (38, 0, 0) normal (1, 0, 0) x (0, 1, 0) in component "01C Wing tip - load adapter"
sketch "Rib at 38 mm sketch (2)" plane through (38, 0, 0) normal (1, 0, 0) x (0, 0, -1) in component "01C Wing tip - load adapter"
  line L0 (0, -32.0662) -> (0, 32.0662)
  line L1 (0, 32.0662) -> (-1.6, 32.0662)
  line L2 (-1.6, 32.0662) -> (-2.6, 27.5769)
  line L3 (-2.6, 27.5769) -> (-6.95, 21.805)
  line L4 (-6.95, 21.805) -> (-6.95, -21.805)
  line L5 (-6.95, -21.805) -> (-3, -28.2183)
  line L6 (-3, -28.2183) -> (-1.6, -32.0662)
  line L7 (-1.6, -32.0662) -> (0, -32.0662)
extrude "Rib at 38 mm'" add sketch "Rib at 38 mm sketch (2)" along normal blind 2.4 bodies 3 in component "01C Wing tip - load adapter"
ref_plane "WorkPlane5" through (36, 0, 0) normal (1, 0, 0) x (0, 1, 0) in component "01C Wing tip - load adapter"
sketch "front short guide at 38 mm sketch (2)" plane through (36, 0, 0) normal (1, 0, 0) x (0, 0, -1) in component "01C Wing tip - load adapter"
  circle A0 centre (-4.5, -18) radius 4.5
extrude "front short guide at 38 mm'" add sketch "front short guide at 38 mm sketch (2)" along normal blind 6 bodies 3 in component "01C Wing tip - load adapter"
sketch "front guide foot at 38 mm sketch (2)" plane through (0, 0, 0) normal (0, 0, 1) x (1, 0, 0) in component "01C Wing tip - load adapter"
  line L0 (36, -21.3) -> (42, -21.3)
  line L1 (42, -21.3) -> (42, -14.7)
  line L2 (42, -14.7) -> (36, -14.7)
  line L3 (36, -14.7) -> (36, -21.3)
extrude "front guide foot at 38 mm'" add sketch "front guide foot at 38 mm sketch (2)" along normal blind 1.4 bodies 3 in component "01C Wing tip - load adapter"
ref_plane "WorkPlane6" through (36, 0, 0) normal (1, 0, 0) x (0, 1, 0) in component "01C Wing tip - load adapter"
sketch "rear short guide at 38 mm sketch (2)" plane through (36, 0, 0) normal (1, 0, 0) x (0, 0, -1) in component "01C Wing tip - load adapter"
  circle A0 centre (-4.5, 18) radius 4.5
extrude "rear short guide at 38 mm'" add sketch "rear short guide at 38 mm sketch (2)" along normal blind 6 bodies 3 in component "01C Wing tip - load adapter"
sketch "rear guide foot at 38 mm sketch (2)" plane through (0, 0, 0) normal (0, 0, 1) x (1, 0, 0) in component "01C Wing tip - load adapter"
  line L0 (36, 14.7) -> (42, 14.7)
  line L1 (42, 14.7) -> (42, 21.3)
  line L2 (42, 21.3) -> (36, 21.3)
  line L3 (36, 21.3) -> (36, 14.7)
extrude "rear guide foot at 38 mm'" add sketch "rear guide foot at 38 mm sketch (2)" along normal blind 1.4 bodies 3 in component "01C Wing tip - load adapter"
ref_plane "WorkPlane7" through (60, 0, 0) normal (1, 0, 0) x (0, 1, 0) in component "01C Wing tip - load adapter"
sketch "Rib at 60 mm sketch (2)" plane through (60, 0, 0) normal (1, 0, 0) x (0, 0, -1) in component "01C Wing tip - load adapter"
  line L0 (0, -31.7576) -> (0, 31.7576)
  line L1 (0, 31.7576) -> (-1.6, 31.7576)
  line L2 (-1.6, 31.7576) -> (-2.6, 27.3115)
  line L3 (-2.6, 27.3115) -> (-6.95, 21.5952)
  line L4 (-6.95, 21.5952) -> (-6.95, -21.5952)
  line L5 (-6.95, -21.5952) -> (-3, -27.9467)
  line L6 (-3, -27.9467) -> (-1.6, -31.7576)
  line L7 (-1.6, -31.7576) -> (0, -31.7576)
extrude "Rib at 60 mm'" add sketch "Rib at 60 mm sketch (2)" along normal blind 2.4 bodies 3 in component "01C Wing tip - load adapter"
ref_plane "WorkPlane8" through (58, 0, 0) normal (1, 0, 0) x (0, 1, 0) in component "01C Wing tip - load adapter"
sketch "front short guide at 60 mm sketch (2)" plane through (58, 0, 0) normal (1, 0, 0) x (0, 0, -1) in component "01C Wing tip - load adapter"
  circle A0 centre (-4.5, -18) radius 4.5
extrude "front short guide at 60 mm'" add sketch "front short guide at 60 mm sketch (2)" along normal blind 6 bodies 3 in component "01C Wing tip - load adapter"
sketch "front guide foot at 60 mm sketch (2)" plane through (0, 0, 0) normal (0, 0, 1) x (1, 0, 0) in component "01C Wing tip - load adapter"
  line L0 (58, -21.3) -> (64, -21.3)
  line L1 (64, -21.3) -> (64, -14.7)
  line L2 (64, -14.7) -> (58, -14.7)
  line L3 (58, -14.7) -> (58, -21.3)
extrude "front guide foot at 60 mm'" add sketch "front guide foot at 60 mm sketch (2)" along normal blind 1.4 bodies 3 in component "01C Wing tip - load adapter"
ref_plane "WorkPlane9" through (58, 0, 0) normal (1, 0, 0) x (0, 1, 0) in component "01C Wing tip - load adapter"
sketch "rear short guide at 60 mm sketch (2)" plane through (58, 0, 0) normal (1, 0, 0) x (0, 0, -1) in component "01C Wing tip - load adapter"
  circle A0 centre (-4.5, 18) radius 4.5
extrude "rear short guide at 60 mm'" add sketch "rear short guide at 60 mm sketch (2)" along normal blind 6 bodies 3 in component "01C Wing tip - load adapter"
sketch "rear guide foot at 60 mm sketch (2)" plane through (0, 0, 0) normal (0, 0, 1) x (1, 0, 0) in component "01C Wing tip - load adapter"
  line L0 (58, 14.7) -> (64, 14.7)
  line L1 (64, 14.7) -> (64, 21.3)
  line L2 (64, 21.3) -> (58, 21.3)
  line L3 (58, 21.3) -> (58, 14.7)
extrude "rear guide foot at 60 mm'" add sketch "rear guide foot at 60 mm sketch (2)" along normal blind 1.4 bodies 3 in component "01C Wing tip - load adapter"
ref_plane "WorkPlane10" through (82, 0, 0) normal (1, 0, 0) x (0, 1, 0) in component "01C Wing tip - load adapter"
sketch "Rib at 82 mm sketch (2)" plane through (82, 0, 0) normal (1, 0, 0) x (0, 0, -1) in component "01C Wing tip - load adapter"
  line L0 (0, -31.4489) -> (0, 31.4489)
  line L1 (0, 31.4489) -> (-1.6, 31.4489)
  line L2 (-1.6, 31.4489) -> (-2.6, 27.0461)
  line L3 (-2.6, 27.0461) -> (-6.95, 21.3853)
  line L4 (-6.95, 21.3853) -> (-6.95, -21.3853)
  line L5 (-6.95, -21.3853) -> (-3, -27.6751)
  line L6 (-3, -27.6751) -> (-1.6, -31.4489)
  line L7 (-1.6, -31.4489) -> (0, -31.4489)
extrude "Rib at 82 mm'" add sketch "Rib at 82 mm sketch (2)" along normal blind 2.4 bodies 3 in component "01C Wing tip - load adapter"
ref_plane "WorkPlane11" through (80, 0, 0) normal (1, 0, 0) x (0, 1, 0) in component "01C Wing tip - load adapter"
sketch "front short guide at 82 mm sketch (2)" plane through (80, 0, 0) normal (1, 0, 0) x (0, 0, -1) in component "01C Wing tip - load adapter"
  circle A0 centre (-4.5, -18) radius 4.5
extrude "front short guide at 82 mm'" add sketch "front short guide at 82 mm sketch (2)" along normal blind 6 bodies 3 in component "01C Wing tip - load adapter"
sketch "front guide foot at 82 mm sketch (2)" plane through (0, 0, 0) normal (0, 0, 1) x (1, 0, 0) in component "01C Wing tip - load adapter"
  line L0 (80, -21.3) -> (86, -21.3)
  line L1 (86, -21.3) -> (86, -14.7)
  line L2 (86, -14.7) -> (80, -14.7)
  line L3 (80, -14.7) -> (80, -21.3)
extrude "front guide foot at 82 mm'" add sketch "front guide foot at 82 mm sketch (2)" along normal blind 1.4 bodies 3 in component "01C Wing tip - load adapter"
ref_plane "WorkPlane12" through (80, 0, 0) normal (1, 0, 0) x (0, 1, 0) in component "01C Wing tip - load adapter"
sketch "rear short guide at 82 mm sketch (2)" plane through (80, 0, 0) normal (1, 0, 0) x (0, 0, -1) in component "01C Wing tip - load adapter"
  circle A0 centre (-4.5, 18) radius 4.5
extrude "rear short guide at 82 mm'" add sketch "rear short guide at 82 mm sketch (2)" along normal blind 6 bodies 3 in component "01C Wing tip - load adapter"
sketch "rear guide foot at 82 mm sketch (2)" plane through (0, 0, 0) normal (0, 0, 1) x (1, 0, 0) in component "01C Wing tip - load adapter"
  line L0 (80, 14.7) -> (86, 14.7)
  line L1 (86, 14.7) -> (86, 21.3)
  line L2 (86, 21.3) -> (80, 21.3)
  line L3 (80, 21.3) -> (80, 14.7)
extrude "rear guide foot at 82 mm'" add sketch "rear guide foot at 82 mm sketch (2)" along normal blind 1.4 bodies 3 in component "01C Wing tip - load adapter"
sketch "Joint landing at 0 sketch (2)" plane through (0, 0, 0) normal (0, 0, 1) x (1, 0, 0) in component "01C Wing tip - load adapter"
  line L0 (0, -10) -> (12, -10)
  line L1 (12, -10) -> (12, 10)
  line L2 (12, 10) -> (0, 10)
  line L3 (0, 10) -> (0, -10)
extrude "Joint landing at 0'" add sketch "Joint landing at 0 sketch (2)" along normal blind 2.4 bodies 3 in component "01C Wing tip - load adapter"
ref_plane "WorkPlane13" through (0, 0, -0.05) normal (0, 0, 1) x (1, 0, 0) in component "01C Wing tip - load adapter"
sketch "Joint bolt at 6 sketch (2)" plane through (0, 0, -0.05) normal (0, 0, 1) x (1, 0, 0) in component "01C Wing tip - load adapter"
  circle A0 centre (6, 0) radius 1.7
  dimension "d319" = 3.4
  measures "d319" diameter of A0
extrude "Joint bolt at 6'" cut sketch "Joint bolt at 6 sketch (2)" along normal blind 2.5 bodies 3 in component "01C Wing tip - load adapter"
sketch "Tip adapter landing sketch" plane through (0, 0, 0) normal (0, 0, 1) x (1, 0, 0) in component "01C Wing tip - load adapter"
  line L0 (98, -26) -> (114, -26)
  line L1 (114, -26) -> (114, 26)
  line L2 (114, 26) -> (98, 26)
  line L3 (98, 26) -> (98, -26)
extrude "Tip adapter landing" add sketch "Tip adapter landing sketch" along normal blind 9 bodies 3 in component "01C Wing tip - load adapter"
sketch "Tip strip shoulder sketch" plane through (0, 0, 0) normal (0, 1, 0) x (1, 0, 0) in component "01C Wing tip - load adapter"
  line L0 (90, 0) -> (98.05, 0)
  line L1 (98.05, 0) -> (98.05, -9)
  line L2 (98.05, -9) -> (90, -2.4)
  line L3 (90, -2.4) -> (90, 0)
extrude "Tip tapered strip shoulder" add sketch "Tip strip shoulder sketch" along normal mid plane 12 bodies 3 in component "01C Wing tip - load adapter"
ref_plane "WorkPlane14" through (0, 0, -0.05) normal (0, 0, 1) x (1, 0, 0) in component "01C Wing tip - load adapter"